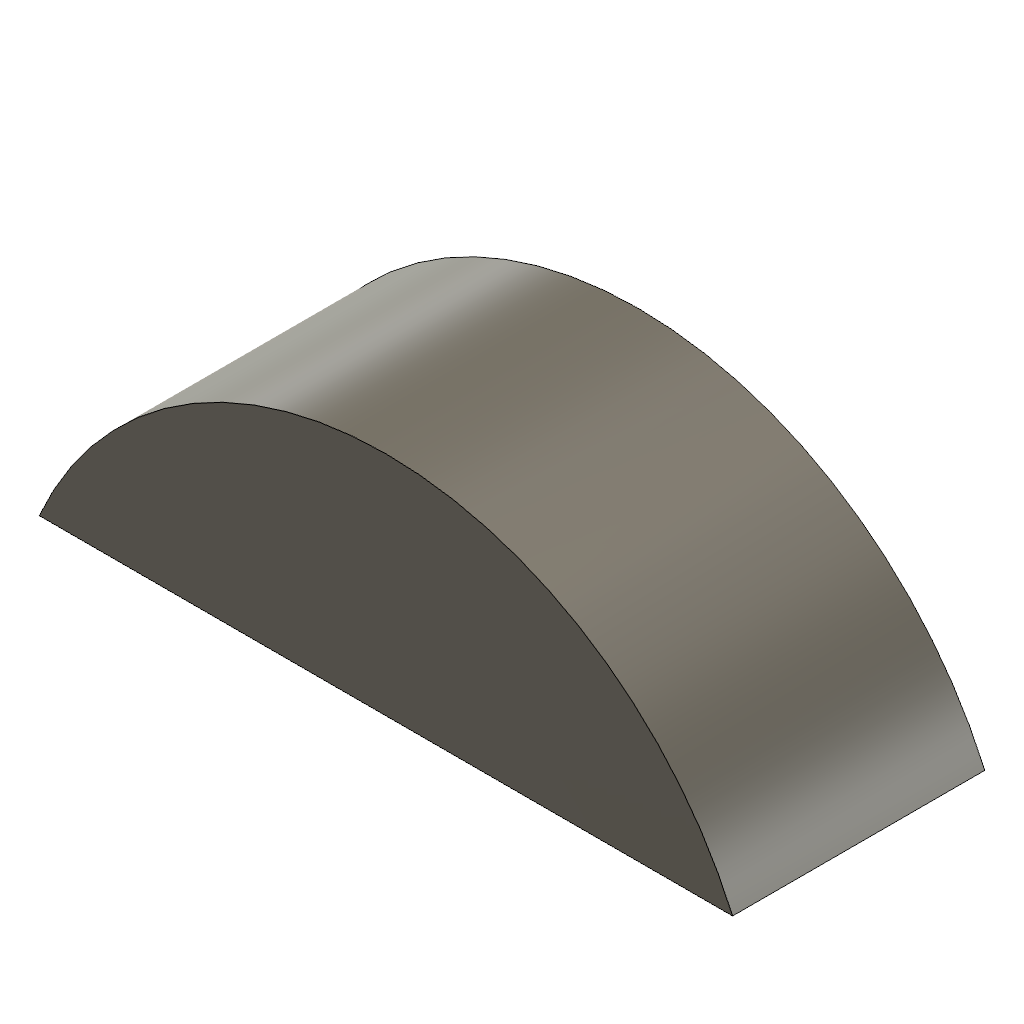
shifted_circle_line_segment (Autodesk Fusion 360 design; units mm, degrees)
part number: 2026-10-21-12-11-54-050
Autodesk Fusion 360 part; units mm, degrees
sketch "TrimmedProfileSources" plane through (0, 0, 0) normal (0, 0, 1) x (1, 0, 0)
  circle A0 centre (10, -10) radius 15
  line L0 (-15, -4) -> (35, -4)
extrude "SelectedTrimmedProfile" add sketch "TrimmedProfileSources" along normal blind 10 contours A0 L0 picked at (10.2161, 1.9178)
